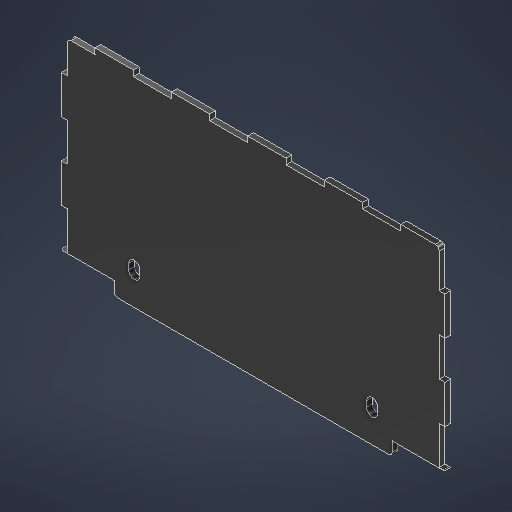
# Autodesk Inventor part: Part2
Saved by Autodesk Inventor 2027.1 (Build 311270010, 270A)
## iProperties
Created: 2026-10-07
Part Number: Part2
Material: MDF Medium Density Fiberboard
Document SubType Name: Modeling
Designer: daniel
Density: 0.8 g/cm^3
Appearance: Glossy - Black
Mass: 47.8224 g
Surface Area: 419.573 cm^2
Volume: 59.7779 cm^3
Author: daniel
Autodesk Inventor part; units mm, degrees
ref_plane "YZ Plane" through (0, 0, 0) normal (1, 0, 0) x (0, 1, 0)
ref_plane "XZ Plane" through (0, 0, 0) normal (0, 1, 0) x (-1, 0, 0)
ref_plane "XY Plane" through (0, 0, 0) normal (0, 0, 1) x (1, 0, 0)
sketch "Sketch1" plane through (0, 0, 0) normal (0, 0, 1) x (1, 0, 0)
  line L0 (26.7826, 135.7478) -> (226.7826, 135.7478)
  line L1 (226.7826, 135.7478) -> (226.7826, 35.7478)
  line L2 (226.7826, 35.7478) -> (26.7826, 35.7478)
  line L3 (26.7826, 35.7478) -> (26.7826, 135.7478)
  line L4 (26.7826, 135.7478) -> (29.7826, 135.7478)
  line L5 (29.7826, 135.7478) -> (29.7826, 115.8478)
  line L6 (29.7826, 115.8478) -> (26.7826, 115.8478)
  line L7 (26.7826, 115.8478) -> (26.7826, 135.7478)
  line L8 (29.7826, 115.8478) -> (26.7826, 115.8478)
  line L9 (26.7826, 115.8478) -> (26.7826, 95.8478)
  line L10 (26.7826, 95.8478) -> (29.7826, 95.8478)
  line L11 (29.7826, 95.8478) -> (29.7826, 115.8478)
  line L12 (26.7826, 95.8478) -> (29.7826, 95.8478)
  line L13 (29.7826, 95.8478) -> (29.7826, 75.9478)
  line L14 (29.7826, 75.9478) -> (26.7826, 75.9478)
  line L15 (26.7826, 75.9478) -> (26.7826, 95.8478)
  line L16 (29.7826, 75.9478) -> (26.7826, 75.9478)
  line L17 (26.7826, 75.9478) -> (26.7826, 55.9478)
  line L18 (26.7826, 55.9478) -> (29.7826, 55.9478)
  line L19 (29.7826, 55.9478) -> (29.7826, 75.9478)
  line L20 (29.7826, 55.9478) -> (26.7826, 55.9478)
  line L21 (26.7826, 55.9478) -> (26.7826, 36.0478)
  line L22 (26.7826, 36.0478) -> (29.7826, 36.0478)
  line L23 (29.7826, 36.0478) -> (29.7826, 55.9478)
  line L24 (26.7826, 36.0478) -> (29.7826, 36.0478)
  line L25 (29.7826, 36.0478) -> (29.7826, 35.7478)
  line L26 (29.7826, 35.7478) -> (26.7826, 35.7478)
  line L27 (26.7826, 35.7478) -> (26.7826, 36.0478)
  line L28 (126.7826, 150.5528) -> (126.7826, -31.6323)
  line L29 (226.7826, 35.7478) -> (226.7826, 135.7478)
  line L30 (226.7826, 135.7478) -> (223.7826, 135.7478)
  line L31 (223.7826, 135.7478) -> (223.7826, 115.8478)
  line L32 (223.7826, 115.8478) -> (226.7826, 115.8478)
  line L33 (226.7826, 115.8478) -> (226.7826, 135.7478)
  line L34 (223.7826, 115.8478) -> (226.7826, 115.8478)
  line L35 (226.7826, 115.8478) -> (226.7826, 95.8478)
  line L36 (226.7826, 95.8478) -> (223.7826, 95.8478)
  line L37 (223.7826, 95.8478) -> (223.7826, 115.8478)
  line L38 (226.7826, 95.8478) -> (223.7826, 95.8478)
  line L39 (223.7826, 95.8478) -> (223.7826, 75.9478)
  line L40 (223.7826, 75.9478) -> (226.7826, 75.9478)
  line L41 (226.7826, 75.9478) -> (226.7826, 95.8478)
  line L42 (223.7826, 75.9478) -> (226.7826, 75.9478)
  line L43 (226.7826, 75.9478) -> (226.7826, 55.9478)
  line L44 (226.7826, 55.9478) -> (223.7826, 55.9478)
  line L45 (223.7826, 55.9478) -> (223.7826, 75.9478)
  line L46 (223.7826, 55.9478) -> (226.7826, 55.9478)
  line L47 (226.7826, 55.9478) -> (226.7826, 36.0478)
  line L48 (226.7826, 36.0478) -> (223.7826, 36.0478)
  line L49 (223.7826, 36.0478) -> (223.7826, 55.9478)
  line L50 (226.7826, 36.0478) -> (223.7826, 36.0478)
  line L51 (223.7826, 36.0478) -> (223.7826, 35.7478)
  line L52 (223.7826, 35.7478) -> (226.7826, 35.7478)
  line L53 (226.7826, 35.7478) -> (226.7826, 36.0478)
  line L54 (223.7826, 135.7478) -> (203.7826, 135.7478)
  line L55 (203.7826, 135.7478) -> (203.7826, 132.7478)
  line L56 (203.7826, 132.7478) -> (223.7826, 132.7478)
  line L57 (223.7826, 132.7478) -> (223.7826, 135.7478)
  line L58 (203.7826, 132.7478) -> (183.8826, 132.7478)
  line L59 (183.8826, 132.7478) -> (183.8826, 135.7478)
  line L60 (183.8826, 135.7478) -> (203.7826, 135.7478)
  line L61 (203.7826, 135.7478) -> (203.7826, 132.7478)
  line L62 (183.8826, 132.7478) -> (163.8826, 132.7478)
  line L63 (163.8826, 132.7478) -> (163.8826, 135.7478)
  line L64 (163.8826, 135.7478) -> (183.8826, 135.7478)
  line L65 (183.8826, 135.7478) -> (183.8826, 132.7478)
  line L66 (163.8826, 132.7478) -> (143.9826, 132.7478)
  line L67 (143.9826, 132.7478) -> (143.9826, 135.7478)
  line L68 (143.9826, 135.7478) -> (163.8826, 135.7478)
  line L69 (163.8826, 135.7478) -> (163.8826, 132.7478)
  line L70 (143.9826, 132.7478) -> (123.9826, 132.7478)
  line L71 (123.9826, 132.7478) -> (123.9826, 135.7478)
  line L72 (123.9826, 135.7478) -> (143.9826, 135.7478)
  line L73 (143.9826, 135.7478) -> (143.9826, 132.7478)
  line L74 (123.9826, 132.7478) -> (104.0826, 132.7478)
  line L75 (104.0826, 132.7478) -> (104.0826, 135.7478)
  line L76 (104.0826, 135.7478) -> (123.9826, 135.7478)
  line L77 (123.9826, 135.7478) -> (123.9826, 132.7478)
  line L78 (104.0826, 132.7478) -> (29.7826, 132.7478)
  line L79 (29.7826, 132.7478) -> (29.7826, 135.7478)
  line L80 (29.7826, 135.7478) -> (104.0826, 135.7478)
  line L81 (104.0826, 135.7478) -> (104.0826, 132.7478)
  line L82 (104.1826, 135.7478) -> (104.1826, 132.7478)
  line L83 (104.1826, 132.7478) -> (84.1826, 132.7478)
  line L84 (84.1826, 132.7478) -> (84.1826, 135.7478)
  line L85 (84.1826, 135.7478) -> (104.1826, 135.7478)
  line L86 (104.1826, 135.7478) -> (104.1826, 132.7478)
  line L87 (84.1826, 132.7478) -> (64.2826, 132.7478)
  line L88 (64.2826, 132.7478) -> (64.2826, 135.7478)
  line L89 (64.2826, 135.7478) -> (84.1826, 135.7478)
  line L90 (84.1826, 135.7478) -> (84.1826, 132.7478)
  line L91 (64.2826, 132.7478) -> (44.2826, 132.7478)
  line L92 (44.2826, 132.7478) -> (44.2826, 135.7478)
  line L93 (44.2826, 135.7478) -> (64.2826, 135.7478)
  line L94 (64.2826, 135.7478) -> (64.2826, 132.7478)
  line L95 (44.2826, 135.7478) -> (44.2826, 132.7478)
  point P0 (0, 0)
  point P1 (29.7826, 95.8478)
  point P2 (26.7826, 75.9478)
  point P3 (226.7826, 36.0478)
  point P4 (226.7826, 55.9478)
  point P5 (226.7826, 75.9478)
  point P6 (223.7826, 95.8478)
  point P7 (226.7826, 95.8478)
  point P8 (226.7826, 115.8478)
  point P9 (223.7826, 135.7478)
  point P10 (26.7826, 115.8478)
  point P11 (26.7826, 95.8478)
  point P12 (203.7826, 135.7478)
  point P13 (225.2826, 135.7478)
  point P14 (225.2826, 115.8478)
  point P15 (225.2826, 115.8478)
  point P16 (225.2826, 95.8478)
  point P17 (27.0826, 150.5528)
  dimension "d0" = 200
  dimension "d1" = 100
  dimension "d2" = 3
  dimension "d3" = 19.9
  dimension "d4" = 20
  dimension "d5" = 3
  dimension "d6" = 19.9
  dimension "d7" = 20
  dimension "d8" = 19.9
  dimension "d11" = 20
  dimension "d12" = 3
  dimension "d13" = 19.9
  dimension "d14" = 20
  dimension "d15" = 19.9
  dimension "d16" = 20
  dimension "d17" = 19.9
  dimension "d18" = 19.9
  dimension "d19" = 20
  dimension "d20" = 3
  dimension "d21" = 20
  dimension "d22" = 19.9
  dimension "d23" = 20
  constraints: 192 end point, 34 parallel, 19 symmetric about line, 17 horizontal, 17 perpendicular, 12 point on line, 4 midpoint, 1 vertical
  measures "d0" distance of L1.end L2.end
  measures "d1" distance of L0.end L1.end
  measures "d2" distance of L5.end L6.end
  measures "d3" distance of L4.end L5.end
  measures "d4" distance of L9.end L8.end
  measures "d5" distance between parallel lines of L11 L9
  measures "d6" distance of L12.end L13.end
  measures "d7" distance of L17.end L16.end
  measures "d8" distance of L21.end L20.end
  measures "d11" distance of L56.end L55.end
  measures "d12" distance of L55.end L54.end
  measures "d13" distance of L59.end L60.end
  measures "d14" distance of L63.end L64.end
  measures "d15" distance of L67.end L68.end
  measures "d16" distance of L71.end L72.end
  measures "d17" distance of L75.end L76.end
  measures "d18" distance of point (225.283, 135.748) point (225.283, 115.848)
  measures "d19" distance of point (225.283, 115.848) point (225.283, 95.848)
  measures "d20" distance of L83.start L82.start
  measures "d21" distance of L85.start L86.start
  measures "d22" distance of L88.end L89.end
  measures "d23" distance of L93.start L93.end
extrude "Extrusion1" add sketch "Sketch1" along normal blind 3 contours L6 L11 L10 L3 | L0 L88 L78 L92 | L78 L74 L70 L28 L2 L25 L23 L19 L13 L11 L5 | L14 L19 L18 L3 | L0 L75 L78 L84 | L22 L25 L2 L3 | L0 L28 L70 L71 | L0 L67 L70 L28 | L28 L70 L66 L62 L58 L56 L31 L37 L39 L45 L49 L51 L2 | L51 L48 L1 L2 | L0 L59 L62 L63 | L45 L40 L1 L44 | L0 L31 L56 L55 | L37 L32 L1 L36
sketch "Sketch2" plane through (0, 0, 0) normal (0, 0, -1) x (-1, 0, 0)
  line L0 (-26.7826, 75.9478) -> (-26.7826, 55.9478) projected
  line L1 (-29.7826, 75.9478) -> (-26.7826, 75.9478) projected
  line L2 (-29.7826, 95.8478) -> (-29.7826, 75.9478) projected
  line L3 (-26.7826, 95.8478) -> (-29.7826, 95.8478) projected
  line L4 (-26.7826, 115.8478) -> (-26.7826, 95.8478) projected
  line L5 (-29.7826, 115.8478) -> (-26.7826, 115.8478) projected
  line L6 (-29.7826, 132.7478) -> (-29.7826, 115.8478) projected
  line L7 (-44.2826, 132.7478) -> (-29.7826, 132.7478) projected
  line L8 (-44.2826, 135.7478) -> (-44.2826, 132.7478) projected
  line L9 (-64.2826, 135.7478) -> (-44.2826, 135.7478) projected
  line L10 (-64.2826, 132.7478) -> (-64.2826, 135.7478) projected
  line L11 (-84.1826, 132.7478) -> (-64.2826, 132.7478) projected
  line L12 (-84.1826, 135.7478) -> (-84.1826, 132.7478) projected
  line L13 (-104.0826, 135.7478) -> (-84.1826, 135.7478) projected
  line L14 (-104.0826, 132.7478) -> (-104.0826, 135.7478) projected
  line L15 (-123.9826, 132.7478) -> (-104.0826, 132.7478) projected
  line L16 (-123.9826, 135.7478) -> (-123.9826, 132.7478) projected
  line L17 (-143.9826, 135.7478) -> (-123.9826, 135.7478) projected
  line L18 (-143.9826, 132.7478) -> (-143.9826, 135.7478) projected
  line L19 (-163.8826, 132.7478) -> (-143.9826, 132.7478) projected
  line L20 (-163.8826, 135.7478) -> (-163.8826, 132.7478) projected
  line L21 (-183.8826, 135.7478) -> (-163.8826, 135.7478) projected
  line L22 (-183.8826, 132.7478) -> (-183.8826, 135.7478) projected
  line L23 (-203.7826, 132.7478) -> (-183.8826, 132.7478) projected
  line L24 (-203.7826, 135.7478) -> (-203.7826, 132.7478) projected
  line L25 (-223.7826, 135.7478) -> (-203.7826, 135.7478) projected
  line L26 (-223.7826, 115.8478) -> (-223.7826, 135.7478) projected
  line L27 (-226.7826, 115.8478) -> (-223.7826, 115.8478) projected
  line L28 (-226.7826, 95.8478) -> (-226.7826, 115.8478) projected
  line L29 (-223.7826, 95.8478) -> (-226.7826, 95.8478) projected
  line L30 (-223.7826, 75.9478) -> (-223.7826, 95.8478) projected
  line L31 (-226.7826, 75.9478) -> (-223.7826, 75.9478) projected
  line L32 (-226.7826, 55.9478) -> (-226.7826, 75.9478) projected
  line L33 (-223.7826, 55.9478) -> (-226.7826, 55.9478) projected
  line L34 (-223.7826, 36.0478) -> (-223.7826, 55.9478) projected
  line L35 (-226.7826, 36.0478) -> (-223.7826, 36.0478) projected
  line L36 (-226.7826, 35.7478) -> (-226.7826, 36.0478) projected
  line L37 (-26.7826, 35.7478) -> (-226.7826, 35.7478) projected
  line L38 (-26.7826, 36.0478) -> (-26.7826, 35.7478) projected
  line L39 (-29.7826, 36.0478) -> (-26.7826, 36.0478) projected
  line L40 (-29.7826, 55.9478) -> (-29.7826, 36.0478) projected
  line L41 (-26.7826, 55.9478) -> (-29.7826, 55.9478) projected
  line L42 (-26.7826, 35.7478) -> (-226.7826, 35.7478) projected
  line L43 (-54.2826, 35.7478) -> (-199.2826, 35.7478)
  line L44 (-199.2826, 35.7478) -> (-199.2826, 30.7478)
  line L45 (-197.2826, 28.7478) -> (-56.2826, 28.7478)
  line L46 (-54.2826, 30.7478) -> (-54.2826, 35.7478)
  arc A0 (-199.2826, 30.7478) -> (-197.2826, 28.7478) centre (-197.2826, 30.7478) ccw
  arc A1 (-56.2826, 28.7478) -> (-54.2826, 30.7478) centre (-56.2826, 30.7478) ccw
  point P0 (0, 0)
  point P1 (-206.9326, 35.7478)
  point P2 (-199.2826, 28.7478)
  point P3 (-54.2826, 28.7478)
  point P4 (-126.7826, 28.7478)
  point P5 (-126.7826, 35.7478)
  dimension "d41" = 145
  dimension "d42" = 7
  dimension "d43" = 2
  constraints: 8 end point, 6 point on line, 4 point on circle, 4 tangent, 2 centre point, 2 midpoint, 2 parallel, 1 equal radius, 1 horizontal, 1 perpendicular, 1 vertical alignment
  measures "d41" distance of point (-54.283, 28.748) point (-199.283, 28.748)
  measures "d42" distance of L43.end point (-199.283, 28.748)
  measures "d43" radius of A0
extrude "Extrusion2" add sketch "Sketch2" against normal blind 3 contours L46 A1 L45 A0 L44 L37
fillet "Fillet1" radius 2 4 edges at (226.7826, 35.7478, 1.5) (223.7826, 135.7478, 1.5) (29.7826, 132.7478, 1.5) (26.7826, 35.7478, 1.5)
sketch "Sketch3" plane through (0, 0, 3) normal (0, 0, 1) x (1, 0, 0)
  arc A0 (26.7826, 36.0478) -> (27.8362, 35.7478) centre (27.8362, 37.7478) ccw projected
  line L0 (27.8362, 35.7478) -> (54.2826, 35.7478) projected
  arc A1 (225.7291, 35.7478) -> (226.7826, 36.0478) centre (225.7291, 37.7478) ccw projected
  line L1 (226.7826, 36.0478) -> (223.7826, 36.0478) projected
  line L2 (223.7826, 36.0478) -> (223.7826, 55.9478) projected
  line L3 (223.7826, 55.9478) -> (226.7826, 55.9478) projected
  line L4 (226.7826, 55.9478) -> (226.7826, 75.9478) projected
  line L5 (226.7826, 75.9478) -> (223.7826, 75.9478) projected
  line L6 (223.7826, 75.9478) -> (223.7826, 95.8478) projected
  line L7 (223.7826, 95.8478) -> (226.7826, 95.8478) projected
  line L8 (226.7826, 95.8478) -> (226.7826, 115.8478) projected
  line L9 (226.7826, 115.8478) -> (223.7826, 115.8478) projected
  line L10 (223.7826, 115.8478) -> (223.7826, 133.7478) projected
  arc A2 (223.7826, 133.7478) -> (221.7826, 135.7478) centre (221.7826, 133.7478) ccw projected
  line L11 (221.7826, 135.7478) -> (203.7826, 135.7478) projected
  line L12 (203.7826, 135.7478) -> (203.7826, 132.7478) projected
  line L13 (203.7826, 132.7478) -> (183.8826, 132.7478) projected
  line L14 (183.8826, 132.7478) -> (183.8826, 135.7478) projected
  line L15 (183.8826, 135.7478) -> (163.8826, 135.7478) projected
  line L16 (163.8826, 135.7478) -> (163.8826, 132.7478) projected
  line L17 (163.8826, 132.7478) -> (143.9826, 132.7478) projected
  line L18 (143.9826, 132.7478) -> (143.9826, 135.7478) projected
  line L19 (143.9826, 135.7478) -> (123.9826, 135.7478) projected
  line L20 (123.9826, 135.7478) -> (123.9826, 132.7478) projected
  line L21 (123.9826, 132.7478) -> (104.0826, 132.7478) projected
  line L22 (104.0826, 132.7478) -> (104.0826, 135.7478) projected
  line L23 (104.0826, 135.7478) -> (84.1826, 135.7478) projected
  line L24 (84.1826, 135.7478) -> (84.1826, 132.7478) projected
  line L25 (84.1826, 132.7478) -> (64.2826, 132.7478) projected
  line L26 (64.2826, 132.7478) -> (64.2826, 135.7478) projected
  line L27 (64.2826, 135.7478) -> (44.2826, 135.7478) projected
  line L28 (44.2826, 135.7478) -> (44.2826, 132.7478) projected
  line L29 (44.2826, 132.7478) -> (31.7826, 132.7478) projected
  arc A3 (31.7826, 132.7478) -> (29.7826, 130.7478) centre (31.7826, 130.7478) ccw projected
  line L30 (29.7826, 130.7478) -> (29.7826, 115.8478) projected
  line L31 (29.7826, 115.8478) -> (26.7826, 115.8478) projected
  line L32 (26.7826, 115.8478) -> (26.7826, 95.8478) projected
  line L33 (26.7826, 95.8478) -> (29.7826, 95.8478) projected
  line L34 (29.7826, 95.8478) -> (29.7826, 75.9478) projected
  line L35 (29.7826, 75.9478) -> (26.7826, 75.9478) projected
  line L36 (26.7826, 75.9478) -> (26.7826, 55.9478) projected
  line L37 (26.7826, 55.9478) -> (29.7826, 55.9478) projected
  line L38 (29.7826, 55.9478) -> (29.7826, 36.0478) projected
  line L39 (29.7826, 36.0478) -> (26.7826, 36.0478) projected
  line L40 (188.7826, 44.2478) -> (188.7826, 47.2478) construction
  line L41 (191.6826, 44.2478) -> (191.6826, 47.2478)
  line L42 (185.8826, 47.2478) -> (185.8826, 44.2478)
  arc A4 (185.8826, 44.2478) -> (191.6826, 44.2478) centre (188.7826, 44.2478) ccw
  arc A5 (191.6826, 47.2478) -> (185.8826, 47.2478) centre (188.7826, 47.2478) ccw
  line L43 (197.2826, 28.7478) -> (56.2826, 28.7478) projected
  line L44 (126.7826, 28.7478) -> (126.7826, 135.7478) construction
  line L45 (64.7826, 44.2478) -> (64.7826, 47.2478) construction
  line L46 (61.8826, 44.2478) -> (61.8826, 47.2478)
  line L47 (67.6826, 47.2478) -> (67.6826, 44.2478)
  arc A6 (61.8826, 44.2478) -> (67.6826, 44.2478) centre (64.7826, 44.2478) ccw
  arc A7 (67.6826, 47.2478) -> (61.8826, 47.2478) centre (64.7826, 47.2478) ccw
  line L48 (199.2826, 35.7478) -> (225.7291, 35.7478) projected
  line L49 (54.2826, 35.7478) -> (54.2826, 30.7478) projected
  arc A8 (54.2826, 30.7478) -> (56.2826, 28.7478) centre (56.2826, 30.7478) ccw projected
  line L50 (56.2826, 28.7478) -> (197.2826, 28.7478) projected
  arc A9 (197.2826, 28.7478) -> (199.2826, 30.7478) centre (197.2826, 30.7478) ccw projected
  line L51 (199.2826, 30.7478) -> (199.2826, 35.7478) projected
  point P0 (0, 0)
  point P1 (188.7826, 45.7478)
  point P2 (64.7826, 45.7478)
  dimension "d44" = 3
  dimension "d45" = 5.8
  dimension "d47" = 35
  dimension "d51" = 8.5
  constraints: 18 end point, 8 point on circle, 7 symmetric about line, 4 centre point, 4 tangent, 2 midpoint, 1 parallel, 1 perpendicular, 1 point on line, 1 vertical, 2 other
  measures "d44" distance of L40.start L40.end
  measures "d45" diameter of A5
  measures "d47" distance from line of L2 point (188.783, 45.748)
  measures "d51" distance from line of L48 L40.start
extrude "Extrusion3" cut sketch "Sketch3" against normal through all contours A4 L42 A5 L41 | L46 A7 L47 A6
equation "\"d3\" = d6"
equation "\"d8\" = d6"
equation "\"d13\" = d6"
equation "\"d15\" = d3"
equation "\"d17\" = d3"
equation "\"d42\" = BaseWoodThickness"
equation "\"d27\" = d26"
equation "\"GridProcutClearance\" = 5"
equation "\"GridBorderThickness\" = 5"
equation "\"GridBorderFillets\" = 7"
equation "\"GridTotalSize\" = 65"
equation "\"GridRobotClearance\" = 65"
equation "\"AluminiumExtrusionClearance\" = 35"
equation "\"BaseTotalLength\" = 885"
equation "\"WorkspaceLength\" = 515"
equation "\"WorkspaceHeight\" = 183"
equation "\"AxesBaseFillet\" = 15"
equation "\"Zaxis\" = 197"
equation "\"ProductTotalHeight\" = 45"
equation "\"VerticalStroke\" = 105"
equation "\"BackArea\" = 165"
equation "\"CylinderStroke\" = 75"
equation "\"BoxesWidth\" = 125"
equation "\"BaseWoodThickness\" = 7"
equation "\"Kerf\" = 0.3"
equation "\"RxThickness\" = 1.8"
equation "\"support_2\" = 265"
equation "\"d26\" = 19.9"
body "Solid1"
